Autodesk Fusion 360 part; units mm, degrees
(part 6 of 18)
  line L3616 (187.99, -95.7008) -> (187.536, -96.0681)
  line L3617 (63.3443, -86.866) -> (63.232, -87.4491)
  line L3618 (179.949, -80.0538) -> (180.521, -79.9348)
  line L3619 (80.4559, -85.4305) -> (80.6591, -85.9784)
  line L3620 (191.051, -87.6844) -> (191.108, -88.266)
  line L3621 (63.495, -86.2917) -> (63.3443, -86.866)
  line L3622 (183.835, -97.7276) -> (183.258, -97.8226)
  line L3623 (189.133, -83.3368) -> (188.753, -82.8812)
  line L3624 (129.124, -88.6312) -> (129.13, -89.225)
  line L3625 (64.9746, -94.459) -> (64.6274, -93.989)
  line L3626 (188.753, -82.8812) -> (188.342, -82.4519)
  line L3627 (75.3734, -80.5239) -> (74.8143, -80.3237)
  line L3628 (187.203, -81.3917) -> (187.673, -81.738)
  line L3629 (188.543, -82.518) -> (188.938, -82.9485)
  line L3630 (142.446, -81.033) -> (141.918, -80.7606)
  line L3631 (63.5618, -91.9156) -> (63.3817, -91.3597)
  line L3632 (175.882, -82.2528) -> (176.32, -81.8668)
  line L3633 (78.5428, -82.518) -> (78.9379, -82.9485)
  line L3634 (64.7274, -83.569) -> (65.0836, -83.1057)
  line L3635 (187.565, -95.9258) -> (188.022, -95.5465)
  line L3636 (70.7068, -80.0004) -> (70.1233, -80.1107)
  line L3637 (176.417, -81.9104) -> (175.97, -82.3007)
  line L3638 (191.125, -89.0237) -> (191.095, -89.6073)
  line L3639 (79.3045, -83.4036) -> (79.6409, -83.8813)
  line L3640 (173.13, -89.225) -> (173.174, -89.8171)
  line L3641 (130.245, -93.1915) -> (130.55, -93.701)
  line L3642 (186.446, -81.033) -> (185.918, -80.7606)
  line L3643 (175.157, -83.166) -> (174.795, -83.6371)
  line L3644 (129.13, -89.225) -> (129.174, -89.8171)
  line L3645 (186.199, -80.7936) -> (186.711, -81.0764)
  line L3646 (146.719, -86.5021) -> (146.544, -85.9345)
  line L3647 (63.0332, -88.6312) -> (63.0347, -88.471)
  line L3648 (185.518, -97.1173) -> (186.059, -96.8711)
  line L3649 (188.342, -82.4519) -> (187.904, -82.0507)
  line L3650 (80.7806, -91.3293) -> (80.6024, -91.8858)
  line L3651 (80.8266, -86.5382) -> (80.9575, -87.1077)
  line L3652 (136.123, -80.1107) -> (135.548, -80.2593)
  line L3653 (131.351, -94.9056) -> (130.975, -94.459)
  line L3654 (132.889, -81.5505) -> (132.417, -81.9104)
  line L3655 (78.8234, -94.8821) -> (78.42, -95.3049)
  line L3656 (145.133, -83.3368) -> (144.753, -82.8812)
  line L3657 (182.483, -79.9042) -> (181.889, -79.897)
  line L3658 (67.6204, -96.7267) -> (67.1214, -96.4227)
  line L3659 (143.441, -81.6795) -> (142.954, -81.3397)
  line L3660 (73.6626, -80.0365) -> (73.075, -79.9508)
  line L3661 (190.456, -85.4305) -> (190.659, -85.9784)
  line L3662 (173.035, -88.471) -> (173.078, -87.8883)
  line L3663 (181.099, -79.8529) -> (181.682, -79.8086)
  line L3664 (74.9634, -97.4273) -> (74.4039, -97.5957)
  line L3665 (77.5358, -96.0681) -> (77.0587, -96.4054)
  line L3666 (130.55, -93.701) -> (130.888, -94.1892)
  line L3667 (69.6987, -97.4835) -> (70.2761, -97.6221)
  line L3668 (78.1207, -82.114) -> (78.5428, -82.518)
  line L3669 (71.682, -79.8086) -> (72.2663, -79.802)
  line L3670 (79.8006, -84.3185) -> (79.4833, -83.8165)
  line L3671 (75.671, -80.5443) -> (76.1995, -80.7936)
  line L3672 (187.059, -96.4054) -> (186.561, -96.7111)
  line L3673 (70.8615, -97.7221) -> (71.4521, -97.7832)
  line L3674 (190.972, -89.8793) -> (191.021, -89.2874)
  line L3675 (136.707, -80.0004) -> (136.123, -80.1107)
  line L3676 (189.57, -93.7534) -> (189.879, -93.246)
  line L3677 (178.985, -80.4458) -> (178.434, -80.6692)
  line L3678 (189.801, -84.3185) -> (189.483, -83.8165)
  line L3679 (178.138, -96.9979) -> (177.62, -96.7267)
  line L3680 (133.018, -96.2389) -> (133.518, -96.5579)
  line L3681 (189.544, -93.963) -> (189.199, -94.4342)
  line L3682 (71.2963, -79.9291) -> (70.7068, -80.0004)
  line L3683 (181.682, -79.8086) -> (182.266, -79.802)
  line L3684 (184.963, -97.3272) -> (185.518, -97.1173)
  line L3685 (186.561, -96.7111) -> (186.044, -96.9841)
  line L3686 (182.639, -97.7873) -> (183.23, -97.7304)
  line L3687 (64.466, -84.1311) -> (64.17, -84.6459)
  line L3688 (184.814, -80.3237) -> (184.243, -80.161)
  line L3689 (181.889, -79.897) -> (181.296, -79.9291)
  line L3690 (70.35, -97.7337) -> (69.7803, -97.6038)
  line L3691 (189.304, -83.4036) -> (189.641, -83.8813)
  line L3692 (179.386, -80.2094) -> (179.949, -80.0538)
  line L3693 (180.927, -97.8266) -> (180.35, -97.7337)
  line L3694 (191.108, -88.266) -> (191.127, -88.85)
  line L3695 (69.1318, -97.3069) -> (69.6987, -97.4835)
  line L3696 (144.453, -95.1378) -> (144.856, -94.7014)
  line L3697 (186.581, -96.5896) -> (187.084, -96.274)
  line L3698 (129.238, -90.7934) -> (129.131, -90.2189)
  line L3699 (176.187, -95.7214) -> (175.756, -95.327)
  line L3700 (64.17, -84.6459) -> (63.9088, -85.1791)
  line L3701 (183.258, -97.8226) -> (182.677, -97.8801)
  line L3702 (20.1085, -84.5595) -> (20.402, -84.0542)
  line L3703 (176.889, -81.5505) -> (176.417, -81.9104)
  line L3704 (175.756, -95.327) -> (175.351, -94.9056)
  line L3705 (138.483, -79.9042) -> (137.889, -79.897)
  line L3706 (174.975, -94.459) -> (174.627, -93.989)
  line L3707 (135.548, -80.2593) -> (134.985, -80.4458)
  line L3708 (173.131, -90.2189) -> (173.061, -89.6388)
  line L3709 (80.9725, -89.8793) -> (81.0211, -89.2874)
  line L3710 (63.7774, -92.4587) -> (63.5618, -91.9156)
  line L3711 (182.046, -97.8049) -> (182.639, -97.7873)
  line L3712 (76.0441, -96.9841) -> (75.5109, -97.2231)
  line L3713 (190.957, -87.1077) -> (191.051, -87.6844)
  line L3714 (129.739, -92.1175) -> (129.974, -92.6629)
  line L3715 (75.1275, -80.3297) -> (75.671, -80.5443)
  line L3716 (19.8482, -85.0827) -> (20.1085, -84.5595)
  line L3717 (63.1297, -89.225) -> (63.1742, -89.8171)
  line L3718 (173.541, -91.5577) -> (173.739, -92.1175)
  line L3719 (173.38, -90.9861) -> (173.541, -91.5577)
  line L3720 (140.814, -80.3237) -> (140.243, -80.161)
  line L3721 (80.9575, -87.1077) -> (81.0514, -87.6844)
  line L3722 (66.1873, -95.7214) -> (65.7561, -95.327)
  line L3723 (146.855, -87.08) -> (146.719, -86.5021)
  line L3724 (64.2446, -93.1915) -> (64.5495, -93.701)
  line L3725 (129.562, -91.9156) -> (129.382, -91.3597)
  line L3726 (80.8551, -87.08) -> (80.7185, -86.5021)
  line L3727 (174.311, -93.4975) -> (174.028, -92.9867)
  line L3728 (137.452, -97.7832) -> (138.046, -97.8049)
  line L3729 (179.132, -97.3069) -> (179.699, -97.4835)
  line L3730 (76.5607, -96.7111) -> (76.0441, -96.9841)
  line L3731 (189.483, -83.8165) -> (189.133, -83.3368)
  line L3732 (177.018, -96.2389) -> (177.518, -96.5579)
  line L3733 (130.17, -84.6459) -> (129.909, -85.1791)
  line L3734 (132.187, -95.7214) -> (131.756, -95.327)
  line L3735 (138.639, -97.7873) -> (139.23, -97.7304)
  line L3736 (65.3513, -94.9056) -> (64.9746, -94.459)
  line L3737 (190.953, -87.6656) -> (190.855, -87.08)
  line L3738 (72.0455, -97.8049) -> (72.6391, -97.7873)
  line L3739 (79.1986, -94.4342) -> (78.8234, -94.8821)
  line L3740 (185.918, -80.7606) -> (185.373, -80.5239)
  line L3741 (132.417, -81.9104) -> (131.97, -82.3007)
  line L3742 (72.2663, -79.802) -> (72.8498, -79.8331)
  line L3743 (129.683, -85.7285) -> (129.495, -86.2917)
  line L3744 (130.627, -93.989) -> (130.311, -93.4975)
  line L3745 (146.972, -89.8793) -> (147.021, -89.2874)
  line L3746 (188.022, -95.5465) -> (188.453, -95.1378)
  line L3747 (130.028, -92.9867) -> (129.777, -92.4587)
  line L3748 (183.43, -79.9018) -> (184.005, -80.0077)
  line L3749 (78.8557, -94.7014) -> (79.2286, -94.2393)
  line L3750 (129.909, -85.1791) -> (129.683, -85.7285)
  line L3751 (68.2951, -80.628) -> (68.8336, -80.4011)
  line L3752 (129.174, -89.8171) -> (129.258, -90.405)
  line L3753 (74.3945, -97.4999) -> (74.9627, -97.3272)
  line L3754 (191.021, -89.2874) -> (191.032, -88.85)
  line L3755 (180.521, -79.9348) -> (181.099, -79.8529)
  line L3756 (182.093, -97.9) -> (181.509, -97.8821)
  line L3757 (80.6024, -91.8858) -> (80.3887, -92.4297)
  line L3758 (188.42, -95.3049) -> (187.99, -95.7008)
  line L3759 (187.084, -96.274) -> (187.565, -95.9258)
  line L3760 (183.816, -97.6345) -> (184.395, -97.4999)
  line L3761 (63.3803, -90.9861) -> (63.541, -91.5577)
  line L3762 (68.5778, -97.0931) -> (69.1318, -97.3069)
  line L3763 (69.9488, -80.0538) -> (70.5208, -79.9348)
  line L3764 (175.657, -95.0931) -> (176.085, -95.5049)
  line L3765 (73.8346, -97.7276) -> (73.2581, -97.8226)
  line L3766 (184.404, -97.5957) -> (183.835, -97.7276)
  line L3767 (147.032, -88.85) -> (147.012, -88.2565)
  line L3768 (80.9531, -87.6656) -> (80.8551, -87.08)
  line L3769 (64.7955, -83.6371) -> (64.466, -84.1311)
  line L3770 (190.922, -90.7625) -> (190.781, -91.3293)
  line L3771 (131.257, -94.6539) -> (131.657, -95.0931)
  line L3772 (67.2676, -81.1835) -> (67.7724, -80.8892)
  line L3773 (187.904, -82.0507) -> (187.441, -81.6795)
  line L3774 (190.781, -91.3293) -> (190.602, -91.8858)
  line L3775 (184.243, -80.161) -> (183.663, -80.0365)
  line L3776 (63.3817, -91.3597) -> (63.2379, -90.7934)
  line L3777 (80.3321, -85.3798) -> (80.084, -84.8403)
  line L3778 (65.0836, -83.1057) -> (65.4688, -82.6664)
  line L3779 (70.5208, -79.9348) -> (71.0994, -79.8529)
  line L3780 (80.6591, -85.9784) -> (80.8266, -86.5382)
  line L3781 (177.121, -96.4227) -> (176.643, -96.0871)
  line L3782 (145.801, -84.3185) -> (145.483, -83.8165)
  line L3783 (71.8893, -79.897) -> (71.2963, -79.9291)
  line L3784 (184.395, -97.4999) -> (184.963, -97.3272)
  line L3785 (73.075, -79.9508) -> (72.483, -79.9042)
  line L3786 (64.3113, -93.4975) -> (64.0276, -92.9867)
  line L3787 (65.157, -83.166) -> (64.7955, -83.6371)
  line L3788 (74.8143, -80.3237) -> (74.2432, -80.161)
  line L3789 (185.671, -80.5443) -> (186.199, -80.7936)
  line L3790 (77.9903, -95.7008) -> (77.5358, -96.0681)
  line L3791 (179.22, -97.4373) -> (178.672, -97.2351)
  line L3792 (147.021, -89.2874) -> (147.032, -88.85)
  line L3793 (130.975, -94.459) -> (130.627, -93.989)
  line L3794 (177.9, -80.9286) -> (177.385, -81.2228)
  line L3795 (173.159, -88.0384) -> (173.124, -88.6312)
  line L3796 (64.1085, -84.5595) -> (64.402, -84.0542)
  line L3797 (129.029, -89.0553) -> (129.033, -88.6312)
  line L3798 (140.243, -80.161) -> (139.663, -80.0365)
  line L3799 (79.6409, -83.8813) -> (79.9457, -84.3798)
  line L3800 (65.9695, -82.3007) -> (65.5489, -82.7199)
  line L3801 (68.8336, -80.4011) -> (69.3856, -80.2094)
  line L3802 (174.108, -84.5595) -> (174.402, -84.0542)
  line L3803 (140.395, -97.4999) -> (140.963, -97.3272)
  line L3804 (190.594, -91.6172) -> (190.758, -91.0467)
  line L3805 (69.5484, -80.2593) -> (68.9847, -80.4458)
  line L3806 (175.084, -83.1057) -> (175.469, -82.6664)
  line L3807 (190.14, -92.9586) -> (189.858, -93.4704)
  line L3808 (191.032, -88.85) -> (191.012, -88.2565)
  line L3809 (185.128, -80.3297) -> (185.671, -80.5443)
  line L3810 (81.1268, -88.85) -> (81.1251, -89.0237)
  line L3811 (65.8816, -82.2528) -> (66.3203, -81.8668)
  line L3812 (190.153, -92.7193) -> (190.391, -92.1756)
  line L3813 (19.4315, -86.1738) -> (19.6222, -85.6215)
  line L3814 (174.466, -84.1311) -> (174.17, -84.6459)
  line L3815 (72.0926, -97.9) -> (71.5085, -97.8821)
  line L3816 (77.0587, -96.4054) -> (76.5607, -96.7111)
  line L3817 (191.095, -89.6073) -> (191.027, -90.1877)
  line L3818 (184.963, -97.4273) -> (184.404, -97.5957)
  line L3819 (81.0951, -89.6073) -> (81.0274, -90.1877)
  line L3820 (129.974, -92.6629) -> (130.245, -93.1915)
  line L3821 (190.855, -87.08) -> (190.719, -86.5021)
  line L3822 (81.0211, -89.2874) -> (81.0318, -88.85)
  line L3823 (129.777, -92.4587) -> (129.562, -91.9156)
  line L3824 (65.4688, -82.6664) -> (65.8816, -82.2528)
  line L3825 (68.9847, -80.4458) -> (68.4345, -80.6692)
  line L3826 (142.581, -96.5896) -> (143.084, -96.274)
  line L3827 (190.544, -85.9345) -> (190.332, -85.3798)
  line L3828 (143.904, -82.0507) -> (143.441, -81.6795)
  line L3829 (63.0612, -89.6388) -> (63.0291, -89.0553)
  line L3830 (74.0047, -80.0077) -> (74.5713, -80.1506)
  line L3831 (190.659, -85.9784) -> (190.827, -86.5382)
  line L3832 (142.954, -81.3397) -> (142.446, -81.033)
  line L3833 (131.657, -95.0931) -> (132.085, -95.5049)
  line L3834 (80.5935, -91.6172) -> (80.7582, -91.0467)
  line L3835 (63.1587, -88.0384) -> (63.1245, -88.6312)
  line L3836 (130.311, -93.4975) -> (130.028, -92.9867)
  line L3837 (189.199, -94.4342) -> (188.823, -94.8821)
  line L3838 (129.541, -91.5577) -> (129.739, -92.1175)
  line L3839 (78.453, -95.1378) -> (78.8557, -94.7014)
  line L3840 (129.258, -90.405) -> (129.38, -90.9861)
  line L3841 (145.879, -93.246) -> (146.153, -92.7193)
  line L3842 (190.084, -84.8403) -> (189.801, -84.3185)
  line L3843 (64.8876, -94.1892) -> (65.2572, -94.6539)
  line L3844 (190.391, -92.1756) -> (190.594, -91.6172)
  line L3845 (178.039, -96.8431) -> (178.578, -97.0931)
  line L3846 (178.434, -80.6692) -> (177.9, -80.9286)
  line L3847 (129.382, -91.3597) -> (129.238, -90.7934)
  line L3848 (132.539, -95.8873) -> (133.018, -96.2389)
  line L3849 (65.6569, -95.0931) -> (66.0847, -95.5049)
  line L3850 (173.061, -89.6388) -> (173.029, -89.0553)
  line L3851 (173.029, -89.0553) -> (173.033, -88.6312)
  line L3852 (77.4411, -81.6795) -> (76.954, -81.3397)
  line L3853 (64.5495, -93.701) -> (64.8876, -94.1892)
  line L3854 (79.4833, -83.8165) -> (79.1334, -83.3368)
  line L3855 (190.827, -86.5382) -> (190.957, -87.1077)
  line L3856 (139.816, -97.6345) -> (140.395, -97.4999)
  line L3857 (79.9457, -84.3798) -> (80.2178, -84.8969)
  line L3858 (80.7185, -86.5021) -> (80.5439, -85.9345)
  line L3859 (176.085, -95.5049) -> (176.539, -95.8873)
  line L3860 (63.6834, -85.7285) -> (63.495, -86.2917)
  line L3861 (77.9045, -82.0507) -> (77.4411, -81.6795)
  line L3862 (80.3914, -92.1756) -> (80.5935, -91.6172)
  line L3863 (139.075, -79.9508) -> (138.483, -79.9042)
  line L3864 (187.441, -81.6795) -> (186.954, -81.3397)
  line L3865 (80.8847, -90.4665) -> (80.9725, -89.8793)
  line L3866 (129.033, -88.6312) -> (129.035, -88.471)
  line L3867 (79.1334, -83.3368) -> (78.7525, -82.8812)
  line L3868 (77.0844, -96.274) -> (77.5654, -95.9258)
  line L3869 (71.0994, -79.8529) -> (71.682, -79.8086)
  line L3870 (144.022, -95.5465) -> (144.453, -95.1378)
  line L3871 (146.084, -84.8403) -> (145.801, -84.3185)
  line L3872 (76.5813, -96.5896) -> (77.0844, -96.274)
  line L3873 (177.385, -81.2228) -> (176.889, -81.5505)
  line L3874 (69.7803, -97.6038) -> (69.2202, -97.4373)
  line L3875 (75.9179, -80.7606) -> (75.3734, -80.5239)
  line L3876 (137.889, -79.897) -> (137.296, -79.9291)
  line L3877 (69.3856, -80.2094) -> (69.9488, -80.0538)
  line L3878 (145.483, -83.8165) -> (145.133, -83.3368)
  line L3879 (79.8585, -93.4704) -> (79.5441, -93.963)
  line L3880 (19.2769, -86.7373) -> (19.4315, -86.1738)
  line L3881 (74.2432, -80.161) -> (73.6626, -80.0365)
  line L3882 (180.707, -80.0004) -> (180.123, -80.1107)
  line L3883 (63.2769, -86.7373) -> (63.4315, -86.1738)
  line L3884 (63.0347, -88.471) -> (63.078, -87.8883)
  line L3885 (80.084, -84.8403) -> (79.8006, -84.3185)
  line L3886 (130.888, -94.1892) -> (131.257, -94.6539)
  line L3887 (63.9088, -85.1791) -> (63.6834, -85.7285)
  line L3888 (173.495, -86.2917) -> (173.344, -86.866)
  line L3889 (189.229, -94.2393) -> (189.57, -93.7534)
  line L3890 (179.548, -80.2593) -> (178.985, -80.4458)
  line L3891 (129.035, -88.471) -> (129.078, -87.8883)
  line L3892 (67.1214, -96.4227) -> (66.643, -96.0871)
  line L3893 (188.856, -94.7014) -> (189.229, -94.2393)
  line L3894 (151.495, -86.2917) -> (151.344, -86.866)
  line L3895 (129.159, -87.3096) -> (129.277, -86.7373)
  line L3896 (159.889, -79.897) -> (159.296, -79.9291)
  line L3897 (152.55, -93.701) -> (152.888, -94.1892)
  line L3898 (43.157, -83.166) -> (42.7955, -83.6371)
  line L3899 (155.9, -80.9286) -> (155.385, -81.2228)
  line L3900 (55.9903, -95.7008) -> (55.5358, -96.0681)
  line L3901 (164.954, -81.3397) -> (164.446, -81.033)
  line L3902 (56.0223, -95.5465) -> (56.453, -95.1378)
  line L3903 (158.276, -97.6221) -> (158.861, -97.7221)
  line L3904 (168.594, -91.6172) -> (168.758, -91.0467)
  line L3905 (165.084, -96.274) -> (165.565, -95.9258)
  line L3906 (43.2572, -94.6539) -> (43.6569, -95.0931)
  line L3907 (55.4411, -81.6795) -> (54.954, -81.3397)
  line L3908 (166.753, -82.8812) -> (166.342, -82.4519)
  line L3909 (144.42, -95.3049) -> (143.99, -95.7008)
  line L3910 (58.3887, -92.4297) -> (58.1404, -92.9586)
  line L3911 (146.456, -85.4305) -> (146.659, -85.9784)
  line L3912 (141.128, -80.3297) -> (141.671, -80.5443)
  line L3913 (152.466, -84.1311) -> (152.17, -84.6459)
  line L3914 (142.199, -80.7936) -> (142.711, -81.0764)
  line L3915 (155.385, -81.2228) -> (154.889, -81.5505)
  line L3916 (42.5495, -93.701) -> (42.8876, -94.1892)
  line L3917 (46.2951, -80.628) -> (46.8336, -80.4011)
  line L3918 (54.7108, -81.0764) -> (55.2028, -81.3917)
  line L3919 (143.203, -81.3917) -> (143.673, -81.738)
  line L3920 (45.3845, -81.2228) -> (44.8893, -81.5505)
  line L3921 (44.417, -81.9104) -> (43.9695, -82.3007)
  line L3922 (47.6987, -97.4835) -> (48.2761, -97.6221)
  line L3923 (154.889, -81.5505) -> (154.417, -81.9104)
  line L3924 (52.9634, -97.4273) -> (52.4039, -97.5957)
  line L3925 (52.5713, -80.1506) -> (53.1275, -80.3297)
  line L3926 (142.711, -81.0764) -> (143.203, -81.3917)
  line L3927 (154.539, -95.8873) -> (155.018, -96.2389)
  line L3928 (144.938, -82.9485) -> (145.304, -83.4036)
  line L3929 (41.541, -91.5577) -> (41.7392, -92.1175)
  line L3930 (49.4521, -97.7832) -> (50.0455, -97.8049)
  line L3931 (54.1995, -80.7936) -> (54.7108, -81.0764)
  line L3932 (136.35, -97.7337) -> (135.78, -97.6038)
  line L3933 (41.9088, -85.1791) -> (41.6834, -85.7285)
  line L3934 (153.157, -83.166) -> (152.795, -83.6371)
  line L3935 (166.453, -95.1378) -> (166.856, -94.7014)
  line L3936 (58.3914, -92.1756) -> (58.5935, -91.6172)
  line L3937 (56.453, -95.1378) -> (56.8557, -94.7014)
  line L3938 (58.3321, -85.3798) -> (58.084, -84.8403)
  line L3939 (137.099, -79.8529) -> (137.682, -79.8086)
  line L3940 (41.1245, -88.6312) -> (41.1297, -89.225)
  line L3941 (55.6734, -81.738) -> (56.1207, -82.114)
  line L3942 (51.2302, -97.7304) -> (51.8162, -97.6345)
  line L3943 (156.434, -80.6692) -> (155.9, -80.9286)
  line L3944 (157.699, -97.4835) -> (158.276, -97.6221)
  line L3945 (160.639, -97.7873) -> (161.23, -97.7304)
  line L3946 (41.6223, -85.6215) -> (41.8482, -85.0827)
  line L3947 (135.78, -97.6038) -> (135.22, -97.4373)
  line L3948 (162.243, -80.161) -> (161.663, -80.0365)
  line L3949 (133.772, -80.8892) -> (134.295, -80.628)
  line L3950 (141.671, -80.5443) -> (142.199, -80.7936)
  line L3951 (155.518, -96.5579) -> (156.039, -96.8431)
  line L3952 (41.495, -86.2917) -> (41.3443, -86.866)
  line L3953 (146.14, -92.9586) -> (145.858, -93.4704)
  line L3954 (151.159, -88.0384) -> (151.124, -88.6312)
  line L3955 (41.0332, -88.6312) -> (41.0347, -88.471)
  line L3956 (134.295, -80.628) -> (134.834, -80.4011)
  line L3957 (145.641, -83.8813) -> (145.946, -84.3798)
  line L3958 (57.8006, -84.3185) -> (57.4833, -83.8165)
  line L3959 (144.121, -82.114) -> (144.543, -82.518)
  line L3960 (54.0441, -96.9841) -> (53.5109, -97.2231)
  line L3961 (162.814, -80.3237) -> (162.243, -80.161)
  line L3962 (165.904, -82.0507) -> (165.441, -81.6795)
  line L3963 (47.3856, -80.2094) -> (47.9488, -80.0538)
  line L3964 (59.1079, -88.266) -> (59.1268, -88.85)
  line L3965 (52.9627, -97.3272) -> (53.5182, -97.1173)
  line L3966 (53.5109, -97.2231) -> (52.9634, -97.4273)
  line L3967 (55.9045, -82.0507) -> (55.4411, -81.6795)
  line L3968 (46.0392, -96.8431) -> (46.5778, -97.0931)
  line L3969 (168.953, -87.6656) -> (168.855, -87.08)
  line L3970 (152.795, -83.6371) -> (152.466, -84.1311)
  line L3971 (151.38, -90.9861) -> (151.541, -91.5577)
  line L3972 (41.1297, -89.225) -> (41.1742, -89.8171)
  line L3973 (129.622, -85.6215) -> (129.848, -85.0827)
  line L3974 (166.856, -94.7014) -> (167.229, -94.2393)
  line L3975 (55.2028, -81.3917) -> (55.6734, -81.738)
  line L3976 (58.6024, -91.8858) -> (58.3887, -92.4297)
  line L3977 (43.9695, -82.3007) -> (43.5489, -82.7199)
  line L3978 (146.781, -91.3293) -> (146.602, -91.8858)
  line L3979 (49.2963, -79.9291) -> (48.7068, -80.0004)
  line L3980 (51.075, -79.9508) -> (50.483, -79.9042)
  line L3981 (156.578, -97.0931) -> (157.132, -97.3069)
  line L3982 (151.739, -92.1175) -> (151.974, -92.6629)
  line L3983 (160.046, -97.8049) -> (160.639, -97.7873)
  line L3984 (42.1085, -84.5595) -> (42.402, -84.0542)
  line L3985 (48.8615, -97.7221) -> (49.4521, -97.7832)
  line L3986 (49.5085, -97.8821) -> (48.9269, -97.8266)
  line L3987 (159.452, -97.7832) -> (160.046, -97.8049)
  line L3988 (41.0347, -88.471) -> (41.078, -87.8883)
  line L3989 (142.561, -96.7111) -> (142.044, -96.9841)
  line L3990 (159.296, -79.9291) -> (158.707, -80.0004)
  line L3991 (55.5358, -96.0681) -> (55.0587, -96.4054)
  line L3992 (41.0291, -89.0553) -> (41.0332, -88.6312)
  line L3993 (155.018, -96.2389) -> (155.518, -96.5579)
  line L3994 (59.1251, -89.0237) -> (59.0951, -89.6073)
  line L3995 (161.663, -80.0365) -> (161.075, -79.9508)
  line L3996 (41.7774, -92.4587) -> (41.5618, -91.9156)
  line L3997 (151.909, -85.1791) -> (151.683, -85.7285)
  line L3998 (56.5428, -82.518) -> (56.9379, -82.9485)
  line L3999 (138.266, -79.802) -> (138.85, -79.8331)
  line L4000 (147.127, -88.85) -> (147.125, -89.0237)
  line L4001 (57.6409, -83.8813) -> (57.9457, -84.3798)
  line L4002 (45.7724, -80.8892) -> (46.2951, -80.628)
  line L4003 (58.1527, -92.7193) -> (58.3914, -92.1756)
  line L4004 (51.8346, -97.7276) -> (51.2581, -97.8226)
  line L4005 (54.0585, -96.8711) -> (54.5813, -96.5896)
  line L4006 (168.885, -90.4665) -> (168.972, -89.8793)
  line L4007 (43.4688, -82.6664) -> (43.8816, -82.2528)
  line L4008 (47.5484, -80.2593) -> (46.9847, -80.4458)
  line L4009 (130.727, -83.569) -> (131.084, -83.1057)
  line L4010 (131.469, -82.6664) -> (131.882, -82.2528)
  line L4011 (42.3113, -93.4975) -> (42.0276, -92.9867)
  line L4012 (42.6274, -93.989) -> (42.3113, -93.4975)
  line L4013 (51.8162, -97.6345) -> (52.3945, -97.4999)
  line L4014 (57.8585, -93.4704) -> (57.5441, -93.963)
  line L4015 (50.8498, -79.8331) -> (51.4301, -79.9018)
  line L4016 (50.6391, -97.7873) -> (51.2302, -97.7304)
  line L4017 (56.3423, -82.4519) -> (55.9045, -82.0507)
  line L4018 (140.005, -80.0077) -> (140.571, -80.1506)
  line L4019 (41.4315, -86.1738) -> (41.6223, -85.6215)
  line L4020 (143.99, -95.7008) -> (143.536, -96.0681)
  line L4021 (43.6569, -95.0931) -> (44.0847, -95.5049)
  line L4022 (165.441, -81.6795) -> (164.954, -81.3397)
  line L4023 (58.084, -84.8403) -> (57.8006, -84.3185)
  line L4024 (46.5778, -97.0931) -> (47.1318, -97.3069)
  line L4025 (153.97, -82.3007) -> (153.549, -82.7199)
  line L4026 (42.9746, -94.459) -> (42.6274, -93.989)
  line L4027 (130.402, -84.0542) -> (130.727, -83.569)
  line L4028 (49.0994, -79.8529) -> (49.682, -79.8086)
  line L4029 (59.0951, -89.6073) -> (59.0274, -90.1877)
  line L4030 (140.963, -97.4273) -> (140.404, -97.5957)
  line L4031 (49.682, -79.8086) -> (50.2663, -79.802)
  line L4032 (41.2578, -90.405) -> (41.3803, -90.9861)
  line L4033 (41.1309, -90.2189) -> (41.0612, -89.6388)
  line L4034 (167.801, -84.3185) -> (167.483, -83.8165)
  line L4035 (46.138, -96.9979) -> (45.6204, -96.7267)
  line L4036 (56.42, -95.3049) -> (55.9903, -95.7008)
  line L4037 (55.5654, -95.9258) -> (56.0223, -95.5465)
  line L4038 (152.245, -93.1915) -> (152.55, -93.701)
  line L4039 (50.6766, -97.8801) -> (50.0926, -97.9)
  line L4040 (41.3443, -86.866) -> (41.2321, -87.4491)
  line L4041 (42.0276, -92.9867) -> (41.7774, -92.4587)
  line L4042 (45.2676, -81.1835) -> (45.7724, -80.8892)
  line L4043 (56.7525, -82.8812) -> (56.3423, -82.4519)
  line L4044 (41.5618, -91.9156) -> (41.3817, -91.3597)
  line L4045 (53.9179, -80.7606) -> (53.3734, -80.5239)
  line L4046 (151.232, -87.4491) -> (151.159, -88.0384)
  line L4047 (138.85, -79.8331) -> (139.43, -79.9018)
  line L4048 (151.974, -92.6629) -> (152.245, -93.1915)
  line L4049 (168.719, -86.5021) -> (168.544, -85.9345)
  line L4050 (47.9488, -80.0538) -> (48.5208, -79.9348)
  line L4051 (52.4039, -97.5957) -> (51.8346, -97.7276)
  line L4052 (136.521, -79.9348) -> (137.099, -79.8529)
  line L4053 (147.125, -89.0237) -> (147.095, -89.6073)
  line L4054 (133.268, -81.1835) -> (133.772, -80.8892)
  line L4055 (53.671, -80.5443) -> (54.1995, -80.7936)
  line L4056 (41.3803, -90.9861) -> (41.541, -91.5577)
  line L4057 (146.922, -90.7625) -> (146.781, -91.3293)
  line L4058 (41.1742, -89.8171) -> (41.2578, -90.405)
  line L4059 (41.9741, -92.6629) -> (42.2446, -93.1915)
  line L4060 (57.5441, -93.963) -> (57.1986, -94.4342)
  line L4061 (57.3045, -83.4036) -> (57.6409, -83.8813)
  line L4062 (58.4559, -85.4305) -> (58.6591, -85.9784)
  line L4063 (56.1207, -82.114) -> (56.5428, -82.518)
  line L4064 (146.389, -92.4297) -> (146.14, -92.9586)
  line L4065 (59.0211, -89.2874) -> (59.0318, -88.85)
  line L4066 (59.1268, -88.85) -> (59.1251, -89.0237)
  line L4067 (52.0047, -80.0077) -> (52.5713, -80.1506)
  line L4068 (44.7829, -81.5099) -> (45.2676, -81.1835)
  line L4069 (57.9457, -84.3798) -> (58.2178, -84.8969)
  line L4070 (48.5208, -79.9348) -> (49.0994, -79.8529)
  line L4071 (48.1233, -80.1107) -> (47.5484, -80.2593)
  line L4072 (135.22, -97.4373) -> (134.672, -97.2351)
  line L4073 (161.23, -97.7304) -> (161.816, -97.6345)
  line L4074 (140.404, -97.5957) -> (139.835, -97.7276)
  line L4075 (45.1214, -96.4227) -> (44.643, -96.0871)
  line L4076 (152.17, -84.6459) -> (151.909, -85.1791)
  line L4077 (156.985, -80.4458) -> (156.434, -80.6692)
  line L4078 (50.0926, -97.9) -> (49.5085, -97.8821)
  line L4079 (158.123, -80.1107) -> (157.548, -80.2593)
  line L4080 (41.3817, -91.3597) -> (41.2379, -90.7934)
  line L4081 (136.927, -97.8266) -> (136.35, -97.7337)
  line L4082 (55.0844, -96.274) -> (55.5654, -95.9258)
  line L4083 (130.108, -84.5595) -> (130.402, -84.0542)
  line L4084 (163.518, -97.1173) -> (164.059, -96.8711)
  line L4085 (144.543, -82.518) -> (144.938, -82.9485)
  line L4086 (151.344, -86.866) -> (151.232, -87.4491)
  line L4087 (154.085, -95.5049) -> (154.539, -95.8873)
  line L4088 (168.391, -92.1756) -> (168.594, -91.6172)
  line L4089 (132.783, -81.5099) -> (133.268, -81.1835)
  line L4090 (140.571, -80.1506) -> (141.128, -80.3297)
  line L4091 (164.446, -81.033) -> (163.918, -80.7606)
  line L4092 (54.954, -81.3397) -> (54.4456, -81.033)
  line L4093 (42.7274, -83.569) -> (43.0836, -83.1057)
  line L4094 (51.2581, -97.8226) -> (50.6766, -97.8801)
  line L4095 (162.963, -97.3272) -> (163.518, -97.1173)
  line L4096 (166.022, -95.5465) -> (166.453, -95.1378)
  line L4097 (151.13, -89.225) -> (151.174, -89.8171)
  line L4098 (135.949, -80.0538) -> (136.521, -79.9348)
  line L4099 (48.9269, -97.8266) -> (48.35, -97.7337)
  line L4100 (56.8234, -94.8821) -> (56.42, -95.3049)
  line L4101 (58.5439, -85.9345) -> (58.3321, -85.3798)
  line L4102 (44.643, -96.0871) -> (44.1873, -95.7214)
  line L4103 (145.858, -93.4704) -> (145.544, -93.963)
  line L4104 (53.3734, -80.5239) -> (52.8143, -80.3237)
  line L4105 (132.32, -81.8668) -> (132.783, -81.5099)
  line L4106 (41.2379, -90.7934) -> (41.1309, -90.2189)
  line L4107 (142.044, -96.9841) -> (141.511, -97.2231)
  line L4108 (59.0274, -90.1877) -> (58.9224, -90.7625)
  line L4109 (167.57, -93.7534) -> (167.879, -93.246)
  line L4110 (58.5935, -91.6172) -> (58.7582, -91.0467)
  line L4111 (41.6834, -85.7285) -> (41.495, -86.2917)
  line L4112 (54.5813, -96.5896) -> (55.0844, -96.274)
  line L4113 (153.257, -94.6539) -> (153.657, -95.0931)
  line L4114 (167.483, -83.8165) -> (167.133, -83.3368)
  line L4115 (164.059, -96.8711) -> (164.581, -96.5896)
  line L4116 (58.6591, -85.9784) -> (58.8266, -86.5382)
  line L4117 (53.5182, -97.1173) -> (54.0585, -96.8711)
  line L4118 (165.565, -95.9258) -> (166.022, -95.5465)
  line L4119 (160.483, -79.9042) -> (159.889, -79.897)
  line L4120 (58.1404, -92.9586) -> (57.8585, -93.4704)
  line L4121 (139.835, -97.7276) -> (139.258, -97.8226)
  line L4122 (129.277, -86.7373) -> (129.432, -86.1738)
  line L4123 (133.62, -96.7267) -> (133.121, -96.4227)
  line L4124 (44.8893, -81.5505) -> (44.417, -81.9104)
  line L4125 (151.174, -89.8171) -> (151.258, -90.405)
  line L4126 (45.9003, -80.9286) -> (45.3845, -81.2228)
  line L4127 (146.827, -86.5382) -> (146.957, -87.1077)
  line L4128 (134.138, -96.9979) -> (133.62, -96.7267)
  line L4129 (58.9531, -87.6656) -> (58.8551, -87.08)
  line L4130 (54.4456, -81.033) -> (53.9179, -80.7606)
  line L4131 (46.672, -97.2351) -> (46.138, -96.9979)
  line L4132 (43.5489, -82.7199) -> (43.157, -83.166)
  line L4133 (59.0514, -87.6844) -> (59.1079, -88.266)
  line L4134 (151.258, -90.405) -> (151.38, -90.9861)
  line L4135 (42.402, -84.0542) -> (42.7274, -83.569)
  line L4136 (153.549, -82.7199) -> (153.157, -83.166)
  line L4137 (47.1318, -97.3069) -> (47.6987, -97.4835)
  line L4138 (59.0121, -88.2565) -> (58.9531, -87.6656)
  line L4139 (41.078, -87.8883) -> (41.1589, -87.3096)
  line L4140 (145.544, -93.963) -> (145.199, -94.4342)
  line L4141 (41.1587, -88.0384) -> (41.1245, -88.6312)
  line L4142 (129.848, -85.0827) -> (130.108, -84.5595)
  line L4143 (58.8266, -86.5382) -> (58.9575, -87.1077)
  line L4144 (168.084, -84.8403) -> (167.801, -84.3185)
  line L4145 (145.304, -83.4036) -> (145.641, -83.8813)
  line L4146 (144.823, -94.8821) -> (144.42, -95.3049)
  line L4147 (134.834, -80.4011) -> (135.386, -80.2094)
  line L4148 (146.957, -87.1077) -> (147.051, -87.6844)
  line L4149 (134.672, -97.2351) -> (134.138, -96.9979)
  line L4150 (163.918, -80.7606) -> (163.373, -80.5239)
  line L4151 (166.342, -82.4519) -> (165.904, -82.0507)
  line L4152 (145.946, -84.3798) -> (146.218, -84.8969)
  line L4153 (137.509, -97.8821) -> (136.927, -97.8266)
  line L4154 (58.9575, -87.1077) -> (59.0514, -87.6844)
  line L4155 (163.373, -80.5239) -> (162.814, -80.3237)
  line L4156 (59.0318, -88.85) -> (59.0121, -88.2565)
  line L4157 (42.7955, -83.6371) -> (42.466, -84.1311)
  line L4158 (43.0836, -83.1057) -> (43.4688, -82.6664)
  line L4159 (52.8143, -80.3237) -> (52.2432, -80.161)
  line L4160 (137.682, -79.8086) -> (138.266, -79.802)
  line L4161 (145.199, -94.4342) -> (144.823, -94.8821)
  line L4162 (129.432, -86.1738) -> (129.622, -85.6215)
  line L4163 (161.816, -97.6345) -> (162.395, -97.4999)
  line L4164 (52.3945, -97.4999) -> (52.9627, -97.3272)
  line L4165 (41.1589, -87.3096) -> (41.2769, -86.7373)
  line L4166 (143.536, -96.0681) -> (143.059, -96.4054)
  line L4167 (143.673, -81.738) -> (144.121, -82.114)
  line L4168 (45.0175, -96.2389) -> (45.5183, -96.5579)
  line L4169 (167.133, -83.3368) -> (166.753, -82.8812)
  line L4170 (44.0847, -95.5049) -> (44.539, -95.8873)
  line L4171 (147.027, -90.1877) -> (146.922, -90.7625)
  line L4172 (135.386, -80.2094) -> (135.949, -80.0538)
  line L4173 (50.2663, -79.802) -> (50.8498, -79.8331)
  line L4174 (168.544, -85.9345) -> (168.332, -85.3798)
  line L4175 (129.078, -87.8883) -> (129.159, -87.3096)
  line L4176 (58.2178, -84.8969) -> (58.4559, -85.4305)
  line L4177 (169.021, -89.2874) -> (169.032, -88.85)
  line L4178 (157.548, -80.2593) -> (156.985, -80.4458)
  line L4179 (43.8816, -82.2528) -> (44.3203, -81.8668)
  line L4180 (151.035, -88.471) -> (151.078, -87.8883)
  line L4181 (51.4301, -79.9018) -> (52.0047, -80.0077)
  line L4182 (169.032, -88.85) -> (169.012, -88.2565)
  line L4183 (44.1873, -95.7214) -> (43.7561, -95.327)
  line L4184 (58.7582, -91.0467) -> (58.8847, -90.4665)
  line L4185 (151.124, -88.6312) -> (151.13, -89.225)
  line L4186 (43.7561, -95.327) -> (43.3513, -94.9056)
  line L4187 (167.879, -93.246) -> (168.153, -92.7193)
  line L4188 (147.108, -88.266) -> (147.127, -88.85)
  line L4189 (54.5607, -96.7111) -> (54.0441, -96.9841)
  line L4190 (151.683, -85.7285) -> (151.495, -86.2917)
  line L4191 (139.43, -79.9018) -> (140.005, -80.0077)
  line L4192 (57.1986, -94.4342) -> (56.8234, -94.8821)
  line L4193 (41.2321, -87.4491) -> (41.1587, -88.0384)
  line L4194 (53.1275, -80.3297) -> (53.671, -80.5443)
  line L4195 (141.511, -97.2231) -> (140.963, -97.4273)
  line L4196 (58.7185, -86.5021) -> (58.5439, -85.9345)
  line L4197 (56.9379, -82.9485) -> (57.3045, -83.4036)
  line L4198 (57.4833, -83.8165) -> (57.1334, -83.3368)
  line L4199 (57.8785, -93.246) -> (58.1527, -92.7193)
  line L4200 (50.483, -79.9042) -> (49.8893, -79.897)
  line L4201 (146.659, -85.9784) -> (146.827, -86.5382)
  line L4202 (152.888, -94.1892) -> (153.257, -94.6539)
  line L4203 (42.466, -84.1311) -> (42.17, -84.6459)
  line L4204 (46.9847, -80.4458) -> (46.4345, -80.6692)
  line L4205 (58.9224, -90.7625) -> (58.7806, -91.3293)
  line L4206 (168.758, -91.0467) -> (168.885, -90.4665)
  line L4207 (167.229, -94.2393) -> (167.57, -93.7534)
  line L4208 (162.395, -97.4999) -> (162.963, -97.3272)
  line L4209 (41.0612, -89.6388) -> (41.0291, -89.0553)
  line L4210 (138.677, -97.8801) -> (138.093, -97.9)
  line L4211 (47.7803, -97.6038) -> (47.2202, -97.4373)
  line L4212 (154.417, -81.9104) -> (153.97, -82.3007)
  line L4213 (48.35, -97.7337) -> (47.7803, -97.6038)
  line L4214 (45.5183, -96.5579) -> (46.0392, -96.8431)
  line L4215 (41.2769, -86.7373) -> (41.4315, -86.1738)
  line L4216 (147.051, -87.6844) -> (147.108, -88.266)
  line L4217 (48.2761, -97.6221) -> (48.8615, -97.7221)
  line L4218 (157.132, -97.3069) -> (157.699, -97.4835)
  line L4219 (47.2202, -97.4373) -> (46.672, -97.2351)
  line L4220 (58.9725, -89.8793) -> (59.0211, -89.2874)
  line L4221 (158.861, -97.7221) -> (159.452, -97.7832)
  line L4222 (55.0587, -96.4054) -> (54.5607, -96.7111)
  line L4223 (58.7806, -91.3293) -> (58.6024, -91.8858)
  line L4224 (168.972, -89.8793) -> (169.021, -89.2874)
  line L4225 (49.8893, -79.897) -> (49.2963, -79.9291)
  line L4226 (46.4345, -80.6692) -> (45.9003, -80.9286)
  line L4227 (51.6626, -80.0365) -> (51.075, -79.9508)
  line L4228 (58.8847, -90.4665) -> (58.9725, -89.8793)
  line L4229 (42.2446, -93.1915) -> (42.5495, -93.701)
  line L4230 (151.541, -91.5577) -> (151.739, -92.1175)
  line L4231 (143.059, -96.4054) -> (142.561, -96.7111)
  line L4232 (169.012, -88.2565) -> (168.953, -87.6656)
  line L4233 (139.258, -97.8226) -> (138.677, -97.8801)
  line L4234 (48.7068, -80.0004) -> (48.1233, -80.1107)
  line L4235 (168.855, -87.08) -> (168.719, -86.5021)
  line L4236 (42.8876, -94.1892) -> (43.2572, -94.6539)
  line L4237 (168.332, -85.3798) -> (168.084, -84.8403)
  line L4238 (147.095, -89.6073) -> (147.027, -90.1877)
  line L4239 (45.6204, -96.7267) -> (45.1214, -96.4227)
  line L4240 (146.602, -91.8858) -> (146.389, -92.4297)
  line L4241 (57.57, -93.7534) -> (57.8785, -93.246)
  line L4242 (164.581, -96.5896) -> (165.084, -96.274)
  line L4243 (161.075, -79.9508) -> (160.483, -79.9042)
  line L4244 (43.3513, -94.9056) -> (42.9746, -94.459)
  line L4245 (168.153, -92.7193) -> (168.391, -92.1756)
  line L4246 (138.093, -97.9) -> (137.509, -97.8821)
  line L4247 (156.039, -96.8431) -> (156.578, -97.0931)
  line L4248 (146.218, -84.8969) -> (146.456, -85.4305)
  line L4249 (44.3203, -81.8668) -> (44.7829, -81.5099)
  line L4250 (57.1334, -83.3368) -> (56.7525, -82.8812)
  line L4251 (56.8557, -94.7014) -> (57.2286, -94.2393)
  line L4252 (42.17, -84.6459) -> (41.9088, -85.1791)
  line L4253 (58.8551, -87.08) -> (58.7185, -86.5021)
  line L4254 (57.2286, -94.2393) -> (57.57, -93.7534)
  line L4255 (50.0455, -97.8049) -> (50.6391, -97.7873)
  line L4256 (46.8336, -80.4011) -> (47.3856, -80.2094)
  line L4257 (131.084, -83.1057) -> (131.469, -82.6664)
  line L4258 (44.539, -95.8873) -> (45.0175, -96.2389)
  line L4259 (158.707, -80.0004) -> (158.123, -80.1107)
  line L4260 (131.882, -82.2528) -> (132.32, -81.8668)
  line L4261 (41.8482, -85.0827) -> (42.1085, -84.5595)
  line L4262 (153.657, -95.0931) -> (154.085, -95.5049)
  line L4263 (52.2432, -80.161) -> (51.6626, -80.0365)
  line L4264 (41.7392, -92.1175) -> (41.9741, -92.6629)
  line L4265 (20.402, -84.0542) -> (20.7274, -83.569)
  line L4266 (107.258, -161.505) -> (107.38, -162.086)
  line L4267 (107.495, -181.092) -> (107.344, -181.666)
  line L4268 (121.565, -167.026) -> (122.022, -166.647)
  line L4269 (122.856, -165.801) -> (123.229, -165.339)
  line L4270 (124.332, -180.18) -> (124.084, -179.64)
  line L4271 (112.138, -191.798) -> (111.62, -191.527)
  line L4272 (85.078, -182.688) -> (85.1589, -182.11)
  line L4273 (107.382, -162.46) -> (107.238, -161.893)
  line L4274 (110.187, -166.821) -> (109.756, -166.427)
  line L4275 (107.777, -163.559) -> (107.562, -163.016)
  line L4276 (100.121, -176.914) -> (100.543, -177.318)
  line L4277 (98.0441, -144.384) -> (97.5109, -144.623)
  line L4278 (108.028, -164.087) -> (107.777, -163.559)
  line L4279 (103.051, -182.484) -> (103.108, -183.066)
  line L4280 (107.035, -159.571) -> (107.078, -158.988)
  line L4281 (121.084, -167.374) -> (121.565, -167.026)
  line L4282 (107.739, -163.217) -> (107.974, -163.763)
  line L4283 (102.602, -186.686) -> (102.389, -187.23)
  line L4284 (107.124, -183.431) -> (107.13, -184.025)
  line L4285 (94.8498, -174.633) -> (95.4301, -174.702)
  line L4286 (120.581, -167.69) -> (121.084, -167.374)
  line L4287 (123.483, -178.617) -> (123.133, -178.137)
  line L4288 (109.657, -189.893) -> (110.085, -190.305)
  line L4289 (122.022, -166.647) -> (122.453, -166.238)
  line L4290 (107.974, -163.763) -> (108.245, -164.291)
  line L4291 (107.238, -161.893) -> (107.131, -161.319)
  line L4292 (123.229, -189.039) -> (123.57, -188.553)
  line L4293 (122.453, -189.938) -> (122.856, -189.501)
  line L4294 (107.541, -162.658) -> (107.739, -163.217)
  line L4295 (118.963, -168.427) -> (119.518, -168.217)
  line L4296 (110.187, -190.521) -> (109.756, -190.127)
  line L4297 (91.7803, -145.004) -> (91.2202, -144.837)
  line L4298 (113.22, -192.237) -> (112.672, -192.035)
  line L4299 (119.518, -191.917) -> (120.059, -191.671)
  line L4300 (107.174, -160.917) -> (107.258, -161.505)
  line L4301 (111.121, -167.523) -> (110.643, -167.187)
  line L4302 (115.452, -168.883) -> (116.046, -168.905)
  line L4303 (120.059, -167.971) -> (120.581, -167.69)
  line L4304 (118.395, -168.6) -> (118.963, -168.427)
  line L4305 (107.131, -185.019) -> (107.061, -184.439)
  line L4306 (108.888, -188.989) -> (109.257, -189.454)
  line L4307 (96.9634, -144.827) -> (96.4039, -144.996)
  line L4308 (109.257, -165.754) -> (109.657, -166.193)
  line L4309 (102.781, -186.129) -> (102.602, -186.686)
  line L4310 (118.814, -175.124) -> (118.243, -174.961)
  line L4311 (108.245, -187.991) -> (108.55, -188.501)
  line L4312 (122.022, -190.347) -> (122.453, -189.938)
  line L4313 (124.391, -163.276) -> (124.594, -162.717)
  line L4314 (103.108, -183.066) -> (103.127, -183.65)
  line L4315 (89.1214, -143.823) -> (88.643, -143.487)
  line L4316 (107.232, -182.249) -> (107.159, -182.838)
  line L4317 (85.8482, -179.883) -> (86.1085, -179.36)
  line L4318 (91.3856, -127.609) -> (91.9488, -127.454)
  line L4319 (123.544, -188.763) -> (123.199, -189.234)
  line L4320 (93.682, -174.609) -> (94.2663, -174.602)
  line L4321 (124.953, -158.766) -> (124.855, -158.18)
  line L4322 (110.643, -167.187) -> (110.187, -166.821)
  line L4323 (124.594, -162.717) -> (124.758, -162.147)
  line L4324 (96.4039, -144.996) -> (95.8346, -145.128)
  line L4325 (102.14, -140.359) -> (101.858, -140.87)
  line L4326 (120.954, -176.14) -> (120.446, -175.833)
  line L4327 (108.888, -165.289) -> (109.257, -165.754)
  line L4328 (111.018, -167.339) -> (111.518, -167.658)
  line L4329 (108.975, -165.559) -> (108.627, -165.089)
  line L4330 (101.544, -141.363) -> (101.199, -141.834)
  line L4331 (103.127, -183.65) -> (103.125, -183.824)
  line L4332 (107.344, -181.666) -> (107.232, -182.249)
  line L4333 (108.028, -187.787) -> (107.777, -187.259)
  line L4334 (92.5208, -174.735) -> (93.0994, -174.653)
  line L4335 (107.029, -183.855) -> (107.033, -183.431)
  line L4336 (111.518, -191.358) -> (112.039, -191.643)
  line L4337 (110.539, -190.687) -> (111.018, -191.039)
  line L4338 (107.159, -182.838) -> (107.124, -183.431)
  line L4339 (99.2028, -176.192) -> (99.6734, -176.538)
  line L4340 (108.466, -178.931) -> (108.17, -179.446)
  line L4341 (107.131, -161.319) -> (107.061, -160.739)
  line L4342 (122.856, -189.501) -> (123.229, -189.039)
  line L4343 (108.245, -164.291) -> (108.55, -164.801)
  line L4344 (117.663, -174.837) -> (117.075, -174.751)
  line L4345 (96.0047, -127.408) -> (96.5713, -127.551)
  line L4346 (102.14, -187.759) -> (101.858, -188.27)
  line L4347 (90.2951, -175.428) -> (90.8336, -175.201)
  line L4348 (99.9903, -143.101) -> (99.5358, -143.468)
  line L4349 (119.518, -168.217) -> (120.059, -167.971)
  line L4350 (98.1995, -175.594) -> (98.7108, -175.876)
  line L4351 (123.57, -164.853) -> (123.879, -164.346)
  line L4352 (109.97, -177.101) -> (109.549, -177.52)
  line L4353 (92.9269, -145.227) -> (92.35, -145.134)
  line L4354 (85.6222, -133.022) -> (85.8482, -132.483)
  line L4355 (115.296, -174.729) -> (114.707, -174.8)
  line L4356 (89.2676, -175.984) -> (89.7724, -175.689)
  line L4357 (112.138, -168.098) -> (111.62, -167.827)
  line L4358 (113.78, -192.404) -> (113.22, -192.237)
  line L4359 (113.548, -175.059) -> (112.985, -175.246)
  line L4360 (121.904, -153.151) -> (121.441, -152.779)
  line L4361 (103.027, -184.988) -> (102.922, -185.562)
  line L4362 (101.199, -189.234) -> (100.823, -189.682)
  line L4363 (125.021, -160.387) -> (125.032, -159.95)
  line L4364 (101.304, -178.204) -> (101.641, -178.681)
  line L4365 (120.446, -175.833) -> (119.918, -175.561)
  line L4366 (112.985, -175.246) -> (112.434, -175.469)
  line L4367 (113.132, -192.107) -> (113.699, -192.283)
  line L4368 (118.395, -192.3) -> (118.963, -192.127)
  line L4369 (95.2581, -145.223) -> (94.6766, -145.28)
  line L4370 (100.42, -190.105) -> (99.9903, -190.501)
  line L4371 (118.963, -192.227) -> (118.404, -192.396)
  line L4372 (123.483, -154.917) -> (123.133, -154.437)
  line L4373 (117.816, -168.734) -> (118.395, -168.6)
  line L4374 (92.5208, -127.335) -> (93.0994, -127.253)
  line L4375 (118.963, -192.127) -> (119.518, -191.917)
  line L4376 (124.084, -155.94) -> (123.801, -155.418)
  line L4377 (100.42, -142.705) -> (99.9903, -143.101)
  line L4378 (112.434, -175.469) -> (111.9, -175.729)
  line L4379 (102.389, -139.83) -> (102.14, -140.359)
  line L4380 (125.021, -184.087) -> (125.032, -183.65)
  line L4381 (108.795, -178.437) -> (108.466, -178.931)
  line L4382 (110.417, -176.71) -> (109.97, -177.101)
  line L4383 (114.276, -168.722) -> (114.861, -168.822)
  line L4384 (102.827, -181.338) -> (102.957, -181.908)
  line L4385 (97.5109, -144.623) -> (96.9634, -144.827)
  line L4386 (117.075, -174.751) -> (116.483, -174.704)
  line L4387 (88.3203, -176.667) -> (88.7829, -176.31)
  line L4388 (122.453, -166.238) -> (122.856, -165.801)
  line L4389 (115.889, -174.697) -> (115.296, -174.729)
  line L4390 (111.518, -167.658) -> (112.039, -167.943)
  line L4391 (116.046, -168.905) -> (116.639, -168.887)
  line L4392 (107.38, -162.086) -> (107.541, -162.658)
  line L4393 (110.643, -190.887) -> (110.187, -190.521)
  line L4394 (122.342, -177.252) -> (121.904, -176.851)
  line L4395 (101.858, -140.87) -> (101.544, -141.363)
  line L4396 (99.5358, -143.468) -> (99.0587, -143.805)
  line L4397 (123.879, -164.346) -> (124.153, -163.819)
  line L4398 (101.199, -141.834) -> (100.823, -142.282)
  line L4399 (123.229, -165.339) -> (123.57, -164.853)
  line L4400 (93.0994, -127.253) -> (93.682, -127.209)
  line L4401 (110.085, -190.305) -> (110.539, -190.687)
  line L4402 (122.42, -190.105) -> (121.99, -190.501)
  line L4403 (109.549, -177.52) -> (109.157, -177.966)
  line L4404 (91.9488, -174.854) -> (92.5208, -174.735)
  line L4405 (114.123, -174.911) -> (113.548, -175.059)
  line L4406 (90.138, -144.398) -> (89.6204, -144.127)
  line L4407 (101.304, -130.804) -> (101.641, -131.281)
  line L4408 (107.238, -185.593) -> (107.131, -185.019)
  line L4409 (93.5085, -145.282) -> (92.9269, -145.227)
  line L4410 (93.0994, -174.653) -> (93.682, -174.609)
  line L4411 (107.174, -184.617) -> (107.258, -185.205)
  line L4412 (115.452, -192.583) -> (116.046, -192.605)
  line L4413 (103.027, -137.588) -> (102.922, -138.162)
  line L4414 (101.858, -188.27) -> (101.544, -188.763)
  line L4415 (87.0836, -130.506) -> (87.4688, -130.066)
  line L4416 (102.922, -138.162) -> (102.781, -138.729)
  line L4417 (118.243, -151.261) -> (117.663, -151.137)
  line L4418 (103.125, -136.424) -> (103.095, -137.007)
  line L4419 (87.8816, -129.653) -> (88.3203, -129.267)
  line L4420 (96.5713, -174.951) -> (97.1275, -175.13)
  line L4421 (119.511, -192.023) -> (118.963, -192.227)
  line L4422 (120.954, -152.44) -> (120.446, -152.133)
  line L4423 (109.351, -189.706) -> (108.975, -189.259)
  line L4424 (113.699, -192.283) -> (114.276, -192.422)
  line L4425 (111.121, -191.223) -> (110.643, -190.887)
  line L4426 (88.3203, -129.267) -> (88.7829, -128.91)
  line L4427 (101.946, -179.18) -> (102.218, -179.697)
  line L4428 (123.858, -188.27) -> (123.544, -188.763)
  line L4429 (96.0047, -174.808) -> (96.5713, -174.951)
  line L4430 (107.061, -160.739) -> (107.029, -160.155)
  line L4431 (98.5607, -144.111) -> (98.0441, -144.384)
  line L4432 (103.051, -135.084) -> (103.108, -135.666)
  line L4433 (121.536, -190.868) -> (121.059, -191.205)
  line L4434 (108.975, -189.259) -> (108.627, -188.789)
  line L4435 (107.029, -160.155) -> (107.033, -159.731)
  line L4436 (103.095, -137.007) -> (103.027, -137.588)
  line L4437 (113.699, -168.583) -> (114.276, -168.722)
  line L4438 (114.707, -174.8) -> (114.123, -174.911)
  line L4439 (89.2676, -128.584) -> (89.7724, -128.289)
  line L4440 (109.257, -189.454) -> (109.657, -189.893)
  line L4441 (107.739, -186.917) -> (107.974, -187.463)
  line L4442 (123.133, -154.437) -> (122.753, -153.981)
  line L4443 (108.17, -179.446) -> (107.909, -179.979)
  line L4444 (119.373, -175.324) -> (118.814, -175.124)
  line L4445 (85.4315, -133.574) -> (85.6222, -133.022)
  line L4446 (102.957, -134.508) -> (103.051, -135.084)
  line L4447 (99.0587, -143.805) -> (98.5607, -144.111)
  line L4448 (119.373, -151.624) -> (118.814, -151.424)
  line L4449 (116.639, -192.587) -> (117.23, -192.53)
  line L4450 (118.243, -174.961) -> (117.663, -174.837)
  line L4451 (100.823, -189.682) -> (100.42, -190.105)
  line L4452 (102.827, -133.938) -> (102.957, -134.508)
  line L4453 (116.483, -174.704) -> (115.889, -174.697)
  line L4454 (103.095, -184.407) -> (103.027, -184.988)
  line L4455 (116.639, -168.887) -> (117.23, -168.83)
  line L4456 (124.758, -185.847) -> (124.885, -185.267)
  line L4457 (93.682, -127.209) -> (94.2663, -127.202)
  line L4458 (86.1085, -131.96) -> (86.402, -131.454)
  line L4459 (96.5713, -127.551) -> (97.1275, -127.73)
  line L4460 (102.218, -132.297) -> (102.456, -132.831)
  line L4461 (103.108, -135.666) -> (103.127, -136.25)
  line L4462 (97.1275, -127.73) -> (97.671, -127.944)
  line L4463 (124.544, -180.735) -> (124.332, -180.18)
  line L4464 (109.756, -190.127) -> (109.351, -189.706)
  line L4465 (115.509, -192.682) -> (114.927, -192.627)
  line L4466 (94.0926, -145.3) -> (93.5085, -145.282)
  line L4467 (97.671, -175.344) -> (98.1995, -175.594)
  line L4468 (100.938, -177.749) -> (101.304, -178.204)
  line L4469 (114.276, -192.422) -> (114.861, -192.522)
  line L4470 (107.033, -159.731) -> (107.035, -159.571)
  line L4471 (110.085, -166.605) -> (110.539, -166.987)
  line L4472 (85.4315, -180.974) -> (85.6222, -180.422)
  line L4473 (110.539, -166.987) -> (111.018, -167.339)
  line L4474 (107.562, -163.016) -> (107.382, -162.46)
  line L4475 (97.1275, -175.13) -> (97.671, -175.344)
  line L4476 (87.4688, -177.466) -> (87.8816, -177.053)
  line L4477 (88.7829, -176.31) -> (89.2676, -175.984)
  line L4478 (107.541, -186.358) -> (107.739, -186.917)
  line L4479 (124.391, -186.976) -> (124.594, -186.417)
  line L4480 (107.382, -186.16) -> (107.238, -185.593)
  line L4481 (100.543, -129.918) -> (100.938, -130.349)
  line L4482 (98.1995, -128.194) -> (98.7108, -128.476)
  line L4483 (123.199, -189.234) -> (122.823, -189.682)
  line L4484 (94.8498, -127.233) -> (95.4301, -127.302)
  line L4485 (120.059, -191.671) -> (120.581, -191.39)
  line L4486 (99.5358, -190.868) -> (99.0587, -191.205)
  line L4487 (119.918, -175.561) -> (119.373, -175.324)
  line L4488 (109.351, -166.006) -> (108.975, -165.559)
  line L4489 (102.456, -180.231) -> (102.659, -180.778)
  line L4490 (114.861, -168.822) -> (115.452, -168.883)
  line L4491 (102.659, -133.378) -> (102.827, -133.938)
  line L4492 (117.23, -168.83) -> (117.816, -168.734)
  line L4493 (124.544, -157.035) -> (124.332, -156.48)
  line L4494 (124.972, -184.679) -> (125.021, -184.087)
  line L4495 (112.578, -168.193) -> (113.132, -168.407)
  line L4496 (124.953, -182.466) -> (124.855, -181.88)
  line L4497 (111.62, -167.827) -> (111.121, -167.523)
  line L4498 (87.0836, -177.906) -> (87.4688, -177.466)
  line L4499 (107.061, -184.439) -> (107.029, -183.855)
  line L4500 (122.342, -153.552) -> (121.904, -153.151)
  line L4501 (107.974, -187.463) -> (108.245, -187.991)
  line L4502 (108.55, -164.801) -> (108.888, -165.289)
  line L4503 (112.039, -167.943) -> (112.578, -168.193)
  line L4504 (124.758, -162.147) -> (124.885, -161.567)
  line L4505 (124.153, -187.519) -> (124.391, -186.976)
  line L4506 (124.14, -187.759) -> (123.858, -188.27)
  line L4507 (92.35, -145.134) -> (91.7803, -145.004)
  line L4508 (125.012, -159.357) -> (124.953, -158.766)
  line L4509 (107.562, -186.716) -> (107.382, -186.16)
  line L4510 (123.801, -179.118) -> (123.483, -178.617)
  line L4511 (116.093, -192.7) -> (115.509, -192.682)
  line L4512 (121.059, -191.205) -> (120.561, -191.511)
  line L4513 (101.946, -131.78) -> (102.218, -132.297)
  line L4514 (85.6222, -180.422) -> (85.8482, -179.883)